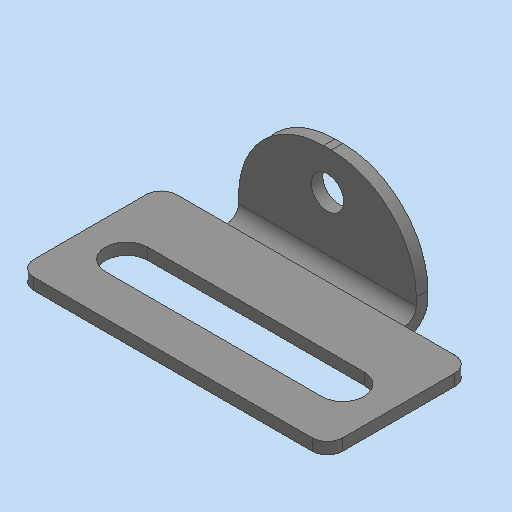
# Autodesk Inventor part: MM0861AN200_G22_222
Saved by Autodesk Inventor 2023.3 (Build 273359000, 359)
## iProperties
RuleStatus: InUse
Created: 2021-05-11
Part Number: MM0861AN200_G22_222
Material: 1.4301 X5CrNi18-10
Description: =<RBPARTNOTITLE2>
Document SubType Name: Blech
Designer: frt9bw
Mass: 10.0124 g
Surface Area: 20.3312 cm^2
Volume: 1.27546 cm^3
Density: 7.85 g/cm^3
Sheet Metal Rule: Standard_mm
Appearance: Stahl - rostfrei AnP
Vendor: ASW
Flat Pattern Width: 3.38929 cm
Flat Pattern Length: 4 cm
Flat Pattern Area: 13.5572 cm^2
Sheet Metal Width: 33,893 mm
Sheet Metal Length: 40,000 mm
Sheet Metal Area: 1355,717 mm^2
AnP_Kategorie: 1
AnP_Material: =<Material>
MaxAbmaße: 15 x 21,5 x 40 (FM)
AnP_TemplVers: 20200821
RBDOCUMENTTYPE: DRF
RBDOCUMENTVERSION: 00
RBDRAWINGMAINSCALE: 1:1
RBDRAWINGMISSINGSPEC: --
RBDRAWINGVOLUME: --
RBDSV1: 0850
RBGBEDGESIN1: +0,5
RBGBEDGESIN2: +0,2
RBGBEDGESOUT1: -0,3
RBGBEDGESOUT2: -0,1
RBMATERIAL: =<Material>
RBMATMEETS: --
RBMATNO: =<Part Number>
RBPARTMADEOF: 15 x 21,5 x 40 (FM)
RBPARTNO: SIEHE MNR
RBPARTNOTITLE1: manufactured part
RBPARTNOTITLE2: Anfertigungsteil
RBPARTSAFETYINDICATOR: --
RBSURFACE: --
RBSURFACE2: --
RBZEDGESNORM: ISO13715:2002-06
RBZGENDIMCLASS: m
RBZGENDIMNORM: ISO 2768-1:1989-11
RBZGENGEOCLASS: H
RBZGENGEONORM: ISO 2768-2:1989-11
RBZSURFACENORM: ISO13D2:2002-02
RBZTOLERANCENORM: ISO 14405-1:2010-12
Author: frt9bw
Keywords: =<RBPARTMADEOF>
Comments: =<RBSURFACE2>
Revision Number: 01
Autodesk Inventor part; units mm, degrees
ref_plane "YZ Plane" through (0, 0, 0) normal (1, 0, 0) x (0, 1, 0)
ref_plane "XZ Plane" through (0, 0, 0) normal (0, 1, 0) x (-1, 0, 0)
ref_plane "XY Plane" through (0, 0, 0) normal (0, 0, 1) x (1, 0, 0)
sketch "Skizze1" plane through (0, 0, 0) normal (0, 0, 1) x (1, 0, 0)
  line L0 (0, 0) -> (40, 0)
  line L1 (40, 0) -> (40, 21.5)
  line L2 (40, 21.5) -> (0, 21.5)
  line L3 (0, 21.5) -> (0, 0)
  dimension "d0" = 40
  dimension "d1" = 21.5
  measures "d0" distance of L2.end L1.end
  measures "d1" distance of L1.end L0.end
extrude "Grobblech1" add sketch "Skizze1" along normal blind 1.5
sketch "Skizze2" plane through (0, 20, 0) normal (0, 1, 0) x (-1, 0, 0)
  line L0 (-40, 0) -> (0, 0)
  line L1 (0, 0) -> (0, 15)
  line L2 (0, 15) -> (-40, 15)
  line L3 (-40, 15) -> (-40, 0)
  constraints: 6 end point, 1 horizontal, 1 perpendicular, 1 vertical
edge flange "Lasche1" height 15 angle 90 thickness 1.5 bend radius 1.5 thickness toward (0, 1, 0) relief tear relief width 1.5 relief depth 0.75 edges at (20, 21.5, 1.5) wall of the first edge with corners at (40, 20, 0) (0, 20, 0) (0, 20, 15) (40, 20, 15)
bend "Biegung1"
corner "Ecke1"
sketch "Skizze3" plane through (40, 20, 3) normal (1, 0, 0) x (0, 0, -1)
  line L0 (0, 0) -> (0, 1.5) projected
  line L1 (0, 1.5) -> (-12, 1.5) projected
  line L2 (-12, 0) -> (-12, 1.5) projected
  line L3 (0, 0) -> (-12, 0) projected
  arc A0 (1.5, -1.5) -> (0, 0) centre (0, -1.5) ccw projected
  line L4 (3, -1.5) -> (1.5, -1.5) projected
  arc A1 (3, -1.5) -> (0, 1.5) centre (0, -1.5) ccw projected
  line L5 (0, 0) -> (0, 1.5) projected
  arc A2 (1.5, -1.5) -> (0, 0) centre (0, -1.5) ccw projected
  line L6 (3, -1.5) -> (1.5, -1.5) projected
  arc A3 (3, -1.5) -> (0, 1.5) centre (0, -1.5) ccw projected
  line L7 (0, 1.5) -> (-12, 1.5) projected
  line L8 (-12, 0) -> (-12, 1.5) projected
  line L9 (0, 0) -> (-12, 0) projected
  point P0 (3, -20)
extrude "Extrusion1" cut sketch "Skizze3" against normal blind 8.5
sketch "Skizze4" plane through (0, 20, 3) normal (-1, 0, 0) x (0, 0, 1)
  line L0 (0, 1.5) -> (0, 0) projected
  arc A0 (0, 1.5) -> (-3, -1.5) centre (0, -1.5) ccw projected
  line L1 (-1.5, -1.5) -> (-3, -1.5) projected
  arc A1 (0, 0) -> (-1.5, -1.5) centre (0, -1.5) ccw projected
  line L2 (0, 0) -> (12, 0) projected
  line L3 (12, 0) -> (12, 1.5) projected
  line L4 (12, 1.5) -> (0, 1.5) projected
  line L5 (0, 0) -> (12, 0) projected
  point P0 (-3, -20)
extrude "Extrusion2" cut sketch "Skizze4" against normal blind 8.5
sketch "Skizze5" plane through (8.5, 20, 3) normal (0, -1, 0) x (1, 0, 0)
  line L0 (0, 12) -> (0, 0) projected
  line L1 (-8.5, -3) -> (31.5, -3) projected
  point P0 (11.5, 7)
  point P1 (0, 1)
  dimension "d18" = 11.5
  dimension "d19" = 10
  measures "d18" distance from line of point (11.5, 7) L0
  measures "d19" distance from line of L1 point (11.5, 7)
hole "Bohrung1" at (20, 20, 10) direction (0, 1, 0) diameter 4.2 depth 1.5 tip angle 118
fillet "Rundung2" radius 11 2 edges at (8.5, 20.75, 15) (31.5, 20.75, 15)
sketch "Skizze6" plane through (0, 0, 1.5) normal (0, 0, 1) x (1, 0, 0)
  line L0 (6, 8) -> (34, 8) construction
  line L1 (6, 5.25) -> (34, 5.25)
  line L2 (34, 10.75) -> (6, 10.75)
  arc A0 (6, 10.75) -> (6, 5.25) centre (6, 8) ccw
  arc A1 (34, 5.25) -> (34, 10.75) centre (34, 8) ccw
  line L3 (0, 0) -> (0, 18.5) projected
  line L4 (40, 0) -> (0, 0) projected
  point P0 (20, 8)
  dimension "d28" = 5.5
  dimension "d29" = 28
  dimension "d30" = 6
  dimension "d31" = 8
  constraints: 8 end point, 4 point on circle, 4 tangent, 2 centre point, 1 horizontal, 1 midpoint, 1 parallel
  measures "d28" diameter of A1
  measures "d29" distance of L0.end L0.start
  measures "d30" distance from line of L0.start L3
  measures "d31" distance from line of point (20, 8) L4
extrude "Extrusion3" cut sketch "Skizze6" against normal through all
fillet "Rundung3" radius 2 4 edges at (0, 0, 0.75) (0, 18.5, 0.75) (40, 18.5, 0.75) (40, 0, 0.75)
equation "\"d25\" = Stärke"
equation "\"d2\" = Stärke"
equation "\"d3\" = BreiteBiegungsfreistellung"
equation "\"d4\" = TiefeBiegungsfreistellung"
equation "\"d5\" = MinimalRest"
equation "\"d6\" = Übergangsradius"
equation "\"d9\" = Biegeradius"
equation "\"d10\" = GrößeEckenfreistellung"
equation "\"d11\" = Abstandsgröße"
equation "\"d12\" = JacobiRadiusGröße"
equation "\"Biegeradius\" = Stärke"
equation "\"BreiteBiegungsfreistellung\" = Stärke"
equation "\"TiefeBiegungsfreistellung\" = 0.5 * Stärke"
equation "\"GrößeEckenfreistellung\" = 4 * Stärke"
equation "\"MinimalRest\" = 2 * Stärke"
equation "\"Übergangsradius\" = Biegeradius"
equation "\"JacobiRadiusGröße\" = Biegeradius"
equation "\"Abstandsgröße\" = Stärke"
equation "\"Stärke\" = 1.5"
